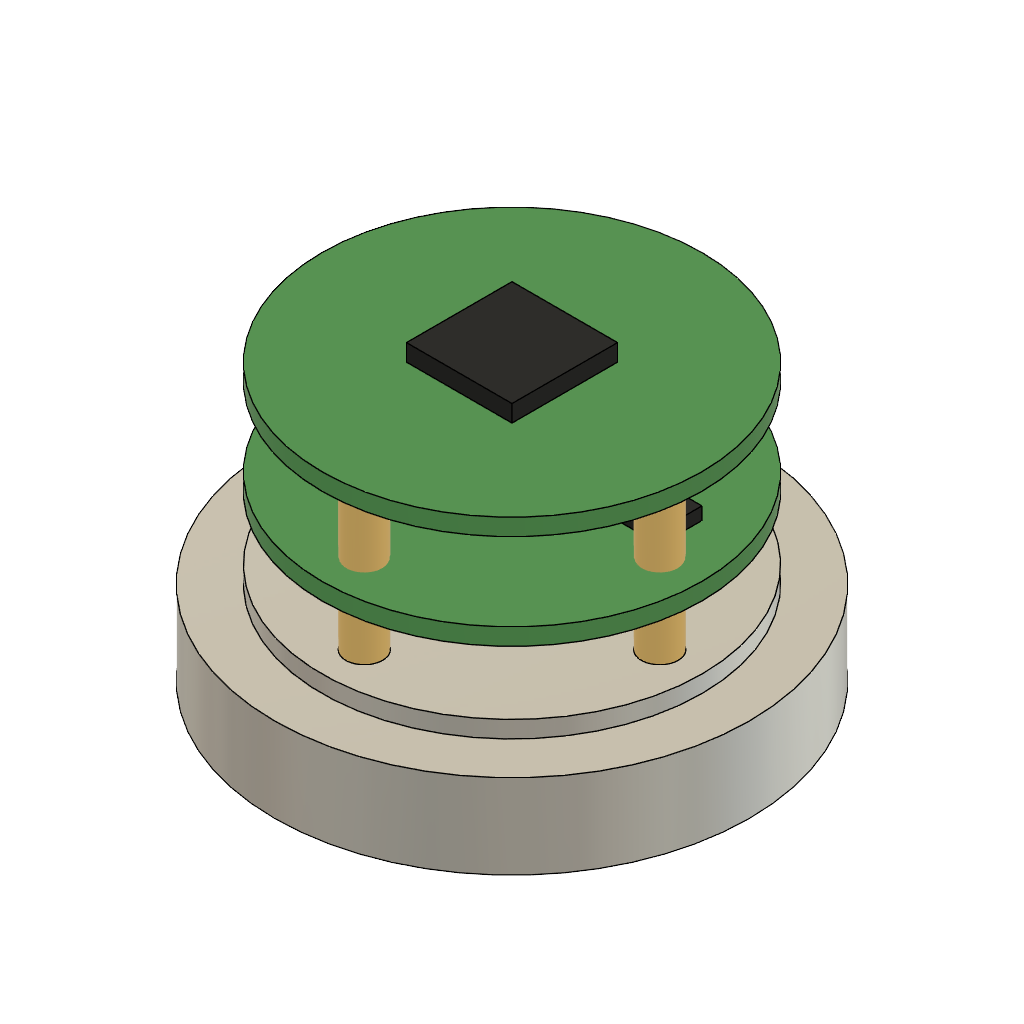
SpikeGuard_CAD (Autodesk Fusion 360 archive; units mm, degrees)
design "Bottom_PCB"
part number: 2026-10-18-21-57-19-919
Autodesk Fusion 360 part; units mm, degrees
sketch "Sketch1" plane through (0, 0, 0) normal (0, 1, 0) x (1, 0, 0)
  circle A0 centre (0, 0) radius 18
  dimension "d1" = 36
  constraint coincident A0.centre origin
  measures "d1" diameter of A0
extrude "Extrude1" add sketch "Sketch1" along normal blind 1.6 makes body 1
ref_plane "WorkPlane1" through (0, -6, 0) normal (0, -1, 0) x (-1, 0, 0)
sketch "Sketch2" plane through (0, -6, 0) normal (0, -1, 0) x (-1, 0, 0)
ref_plane "WorkPlane2" through (0, -6, 0) normal (0, -1, 0) x (-1, 0, 0)
sketch "Sketch3" plane through (0, -6, 0) normal (0, -1, 0) x (-1, 0, 0)
  circle A0 centre (0, 0) radius 18
  dimension "d8" = 36
  constraint coincident A0.centre origin
  measures "d8" diameter of A0
extrude "Extrude2" add sketch "Sketch3" along normal blind 1.6 separate body makes body 2
sketch "Sketch4" plane through (0, 1.6, 0) normal (0, 1, 0) x (-1, 0, 0)
  circle A0 centre (0, 0) radius 18
  line L0 (0, 0) -> (5, 0)
  line L1 (5, 0) -> (5, -5)
  line L2 (5, -5) -> (0, -5)
  line L3 (0, -5) -> (0, 0)
  line L4 (-13, -1) -> (-7, -1)
  line L5 (-7, -1) -> (-7, -5)
  line L6 (-7, -5) -> (-13, -5)
  line L7 (-13, -5) -> (-13, -1)
  line L8 (8, -1) -> (12, -1)
  line L9 (12, -1) -> (12, -5)
  line L10 (12, -5) -> (8, -5)
  line L11 (8, -5) -> (8, -1)
  dimension "d11" = 5
  dimension "d12" = 5
  dimension "d13" = 6
  dimension "d14" = 4
  dimension "d15" = 4
  constraint horizontal L0
  constraint vertical L1
  constraint horizontal L2
  constraint vertical L3
  constraint coincident A0.centre L0.start
  constraint horizontal L4
  constraint vertical L5
  constraint horizontal L6
  constraint vertical L7
  constraint horizontal L8
  constraint vertical L9
  constraint horizontal L10
  constraint vertical L11
  measures "d11" distance of A0.centre L0.end
  measures "d12" distance of A0.centre L2.end
  measures "d13" distance of L4.start L4.end
  measures "d14" distance of L4.start L6.end
  measures "d15" distance of L8.start L8.end
extrude "Extrude3" add sketch "Sketch4" along normal blind 1.2 separate body contours L0 L1 L2 L3 | L4 L5 L6 L7 | L8 L9 L10 L11 makes body 3 at (11, 1.6, -2.3333) makes body 4 at (-1.6667, 1.6, -1.6667) makes body 5 at (-9.3333, 1.6, -2.3333)
sketch "Sketch5" plane through (0, -6, 0) normal (0, 1, 0) x (-1, 0, 0)
  circle A0 centre (0, 0) radius 18
  circle A1 centre (16, 0) radius 1.75
  dimension "d18" = 3.5
  measures "d18" diameter of A1
sketch "Sketch6" plane through (0, -6, 0) normal (0, 1, 0) x (-1, 0, 0)
  circle A0 centre (0, -13) radius 1.75
  circle A1 centre (-14, 0) radius 1.75
  circle A2 centre (0, 14) radius 1.75
  dimension "d19" = 3.5
  dimension "d20" = 3.5
  dimension "d21" = 3.5
  measures "d19" diameter of A0
  measures "d20" diameter of A1
  measures "d21" diameter of A2
extrude "Extrude4" add sketch "Sketch6" sketch "Sketch5" along normal blind 15 separate body of sketch 2 contours A1 makes body 6 at (-1.7413, 4, 13.8258) makes body 7 at (12.2587, 4, -0.1742) makes body 8 at (-1.7413, 4, -13.1742) makes body 9 at (-17.7413, 4, -0.1742)
sketch "Sketch7" plane through (0, 9, 0) normal (0, 1, 0) x (-1, 0, 0)
  circle A0 centre (-14, 0) radius 1.75
  circle A1 centre (0, 0) radius 18
  dimension "d24" = 36
  constraint coincident A1.centre origin
  measures "d24" diameter of A1
extrude "Extrude5" add sketch "Sketch7" along normal blind 1.6 separate body contours A0 | A1 makes body 10
sketch "Sketch8" plane through (0, 10.6, 0) normal (0, 1, 0) x (-1, 0, 0)
  circle A0 centre (0, 0) radius 18
  line L0 (5, -5) -> (-5, -5)
  line L1 (-5, -5) -> (-5, 5)
  line L2 (-5, 5) -> (5, 5)
  line L3 (5, 5) -> (5, -5)
  line L4 (5, -5) -> (-5, 5) construction
  line L5 (-5, -5) -> (5, 5) construction
  dimension "d27" = 10
  dimension "d28" = 10
  constraint horizontal L0
  constraint perpendicular L0 L1
  constraint parallel L0 L2
  constraint parallel L1 L3
  constraint coincident L4 A0.centre
  constraint coincident L5 A0.centre
  constraint coincident A0.centre origin
  measures "d27" distance of L1.end L2.end
  measures "d28" distance of L0.end L1.end
sketch "Sketch9" plane through (0, -7.6, 0) normal (0, -1, 0) x (1, 0, 0)
  circle A0 centre (0, 0) radius 18
  circle A1 centre (0, 0) radius 22.5
  dimension "d31" = 45
  constraint concentric A0 A1
  measures "d31" diameter of A1
extrude "Extrude7" add sketch "Sketch9" along normal blind 8 contours A0 | A1 bodies 2
sketch "Sketch10" plane through (0, 10.6, 0) normal (0, 1, 0) x (-1, 0, 0)
  circle A0 centre (0, 0) radius 18
  line L0 (-5, 5) -> (5, 5)
  line L1 (5, 5) -> (5, -5)
  line L2 (5, -5) -> (-5, -5)
  line L3 (-5, -5) -> (-5, 5)
  line L4 (-5, 5) -> (5, -5) construction
  line L5 (5, 5) -> (-5, -5) construction
  dimension "d34" = 10
  dimension "d35" = 10
  constraint horizontal L0
  constraint perpendicular L0 L1
  constraint parallel L0 L2
  constraint parallel L1 L3
  constraint coincident L4 A0.centre
  constraint coincident L5 A0.centre
  constraint coincident A0.centre origin
  measures "d34" distance of L1.end L2.end
  measures "d35" distance of L0.end L1.end
extrude "Extrude8" add sketch "Sketch10" along normal blind 1.6 separate body contours L0 L1 L2 L3 makes body 11
